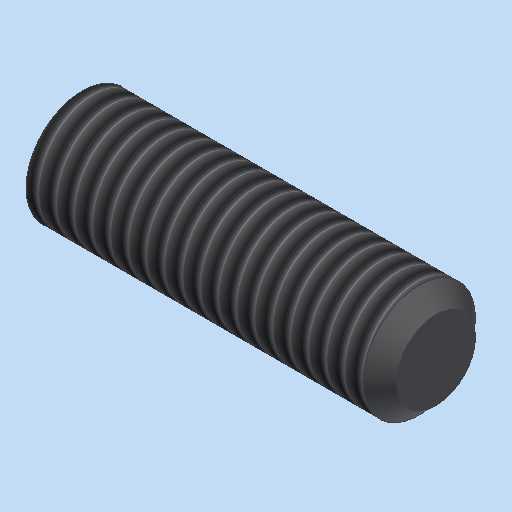
# Autodesk Inventor part: MM0948AN140_G02_100
Saved by Autodesk Inventor 2023.3 (Build 273359000, 359)
## iProperties
Shininess: 64.0
Length Units: 11269
Angle Units: 11279
Time Units: 11290
Mass Units: 11283
Length Display Precision: 3
Angle Display Precision: 2
Compacted: True
Part Number: MM0948AN140_G02_100
Document SubType Name: Modeling
Created: 2004-03-23
Material: xAlu_AnP_Dummymaterial
Description: =<RBPARTNOTITLE2>
Vendor: --
Designer: S.Riedelsheimer
Manufacturer: Standard
Standards Organization: Custom
Density: 2.7 g/cm^3
Mass: 0.790765 g
Surface Area: 3.05112 cm^2
Volume: 0.292876 cm^3
Appearance: Stahl - normal AnP
Density: 0.0
Volumn: 0.0
Area: 0.0
PropertySet Name: Model Information
Control State: 0
Master: False
Checked Out: False
CNS_NB: Gewindestift DIN 913 - M5x16
CNS_NN: DIN 913
CNS_NT: Gewindestift mit Innensechskant und Kegelkuppe
CNS_NBSYN: Gewindestift DIN 913 - $NENN.
CNS_LINA: Gewindestift DIN 913 - M5x16
CNS_NENN: M5x16
CNS_D: 5.000
CNS_D3: 4.019
CNS_P: 0.800
CNS_L: 16.000
CNS_DP: 3.500
CNS_S: 2.500
CNS_T: 3.000
CNS_KT: X
PSOL_IDENT_0: {C:\partsolutions8\data\23d-libs\bosch_bamberg\schrauben\gewindestifte\din_913.prj},164 {M=Nenngewin
PSOL_IDENT_1: de},{VTYP=3D},{NB=Gewindestift DIN 913 - M5x16},{NN=DIN 913},{DATE=26.11.2003},{GEOMDATE=26.11.2003}
PSOL_IDENT_2: ,{VERSION=v1},{LINEID=450},{LINESUBID=-1},{WBVAR=}  {NB=Gewindestift DIN 913 - M5x16},{LINA=Gewindes
PSOL_IDENT_3: tift DIN 913 - M5x16},{KT=X},{IDNR=},{NENN=M5x16},{D=5.000},{D3=4.019},{P=0.800},{L=16.000},{DP=3.50
PSOL_IDENT_4: 0},{S=2.500},{T=3.000}
RBDRAWINGMISSINGSPEC: --
RBPARTNOTITLE2: Schweissbolzen
AnP_Kategorie: 2
RBPARTNOTITLE1: welding stud
RBPARTMADEOF: Schweissbolzen M5 x 16 (Alu)
RBSURFACE2: --
RBSURFACE: --
AnP_Material: =<Material>
RBMATERIAL: --
MaxAbmaße: 5 x 5 x 16 (FM)
Title: Gewindestift DIN 913 - M5x16
Author: S.Riedelsheimer
Keywords: =<RBPARTMADEOF>
Comments: =<RBSURFACE2>
Revision Number: 01
Autodesk Inventor part; units mm, degrees
sketch "Sketch_1" plane through (0, 0, 0) normal (0, 0, 1) x (1, 0, 0)
  line L0 (0.8333, 0) -> (16, 0)
  line L1 (16, 0) -> (16, -1.75)
  line L2 (16, -1.75) -> (15.25, -2.5)
  line L3 (15.25, -2.5) -> (0.2832, -2.5)
  line L4 (0.2832, -2.5) -> (0, -2.0095)
  line L5 (0, -2.0095) -> (0, -1.4434)
  line L6 (0, -1.4434) -> (0.8333, 0)
  line L7 (0.8333, 0) -> (16, 0)
  constraints: 16 end point
revolve "Drehung1" add sketch "Sketch_1" angle 360 about axis through (0.8333, 0, 0) along (1, 0, 0)
thread "Gewinde1" size "M5x0.8" class "6g" standard "ANSI Metric M Profile" length 15.7405
sketch "Sketch_2" plane through (0, 0, 0) normal (1, 0, 0) x (0, 1, 0)
  line L0 (0, 1.4434) -> (-1.25, 0.7217)
  line L1 (-1.25, 0.7217) -> (-1.25, -0.7217)
  line L2 (-1.25, -0.7217) -> (0, -1.4434)
  line L3 (0, -1.4434) -> (1.25, -0.7217)
  line L4 (1.25, -0.7217) -> (1.25, 0.7217)
  line L5 (1.25, 0.7217) -> (0, 1.4434)
  constraints: 12 end point
extrude "Extrusion1" cut sketch "Sketch_2" along normal blind 3
ref_plane "IP1_XY" through (0, 0, 0) normal (1, 0, 0) x (0, 0, -1)
ref_plane "IP1_YZ" through (0, 0, 0) normal (0, 0, -1) x (0, 1, 0)
ref_plane "IP2_XY" through (16, 0, 0) normal (1, 0, 0) x (0, 0, -1)
ref_plane "IP2_YZ" through (16, 0, 0) normal (0, 0, -1) x (0, 1, 0)
